Autodesk Fusion 360 part; units mm, degrees
(part 2 of 5)
extrude "B Facet 45 Opening 2" cut sketch "B Facet 45 Triangle 2" against normal blind 4.7 bodies 4 in component "B Moving Body"
fillet "B Facet 45 Aperture Root Radii" radius 1.5 6 edges at (-120, 35.1319, 67.7522) (-56.8709, 35.1319, 67.7522) (-120, 65.2593, 37.6247) (-110.9231, 67.7522, 35.1319) (-59.6927, 43.3032, 59.5808) (-84.1416, 67.7522, 35.1319) on bodies 4 in component "B Moving Body"
ref_plane "WorkPlane5" through (12.125, 0, 0) normal (0, 0, 1) x (1, 0, 0) in component "B Moving Body"
ref_plane "WorkPlane6" through (12.125, 0, 75) normal (0, 0, 1) x (1, 0, 0) in component "B Moving Body"
sketch "B Facet 90 Triangle 1" plane through (0, 0, 75) normal (0, 0, 1) x (1, 0, 0) in component "B Moving Body"
  line L0 (17.1665, -27.066) -> (-36.9655, 27.066) construction
  line L1 (-36.9655, 27.066) -> (-53.4167, -27.066) construction
  line L2 (-53.4167, -27.066) -> (17.1665, -27.066) construction
  line L3 (7.5097, -23.066) -> (-35.0777, 19.5214)
  line L4 (-35.0777, 19.5214) -> (-48.0205, -23.066)
  line L5 (-48.0205, -23.066) -> (7.5097, -23.066)
  dimension "d384" = 17.1665
  dimension "d385" = 27.066
  dimension "d386" = 36.9655
  dimension "d387" = 27.066
  dimension "d388" = 53.4167
  dimension "d389" = 27.066
  dimension "d390" = -4
  measures "d384" horizontal distance of origin L0.start
  measures "d385" vertical distance of origin L0.start
  measures "d386" horizontal distance of origin L0.end
  measures "d387" vertical distance of origin L0.end
  measures "d388" horizontal distance of origin L1.end
  measures "d389" vertical distance of origin L1.end
extrude "B Facet 90 Opening 1" cut sketch "B Facet 90 Triangle 1" against normal blind 4.7 bodies 4 in component "B Moving Body"
sketch "B Facet 90 Triangle 2" plane through (0, 0, 75) normal (0, 0, 1) x (1, 0, 0) in component "B Moving Body"
  line L0 (-36.9655, 27.066) -> (-53.4167, -27.066) construction
  line L1 (-53.4167, -27.066) -> (-124, 27.066) construction
  line L2 (-124, 27.066) -> (-36.9655, 27.066) construction
  line L3 (-42.3618, 23.066) -> (-55.5648, -20.3777)
  line L4 (-55.5648, -20.3777) -> (-112.2115, 23.066)
  line L5 (-112.2115, 23.066) -> (-42.3618, 23.066)
  dimension "d393" = 36.9655
  dimension "d394" = 27.066
  dimension "d395" = 53.4167
  dimension "d396" = 27.066
  dimension "d397" = 124
  dimension "d398" = 27.066
  dimension "d399" = 4
  measures "d393" horizontal distance of origin L0.start
  measures "d394" vertical distance of origin L0.start
  measures "d395" horizontal distance of origin L0.end
  measures "d396" vertical distance of origin L0.end
  measures "d397" horizontal distance of origin L1.end
  measures "d398" vertical distance of origin L1.end
extrude "B Facet 90 Opening 2" cut sketch "B Facet 90 Triangle 2" against normal blind 4.7 bodies 4 in component "B Moving Body"
sketch "B Facet 90 Triangle 3" plane through (0, 0, 75) normal (0, 0, 1) x (1, 0, 0) in component "B Moving Body"
  line L0 (-53.4167, -27.066) -> (-124, 27.066) construction
  line L1 (-124, 27.066) -> (-124, -27.066) construction
  line L2 (-124, -27.066) -> (-53.4167, -27.066) construction
  line L3 (-65.2053, -23.066) -> (-120, 18.9574)
  line L4 (-120, 18.9574) -> (-120, -23.066)
  line L5 (-120, -23.066) -> (-65.2053, -23.066)
  dimension "d402" = 53.4167
  dimension "d403" = 27.066
  dimension "d404" = 124
  dimension "d405" = 27.066
  dimension "d406" = 124
  dimension "d407" = 27.066
  dimension "d408" = -4
  measures "d402" horizontal distance of origin L0.start
  measures "d403" vertical distance of origin L0.start
  measures "d404" horizontal distance of origin L0.end
  measures "d405" vertical distance of origin L0.end
  measures "d406" horizontal distance of origin L1.end
  measures "d407" vertical distance of origin L1.end
extrude "B Facet 90 Opening 3" cut sketch "B Facet 90 Triangle 3" against normal blind 4.7 bodies 4 in component "B Moving Body"
fillet "B Facet 90 Aperture Root Radii" radius 1.5 9 edges at (-120, -23.066, 72.75) (-65.2053, -23.066, 72.75) (-120, 18.9574, 72.75) (-112.2115, 23.066, 72.75) (-55.5648, -20.3777, 72.75) (-42.3618, 23.066, 72.75) (-48.0205, -23.066, 72.75) (7.5097, -23.066, 72.75) (-35.0777, 19.5214, 72.75) on bodies 4 in component "B Moving Body"
ref_plane "WorkPlane7" through (12.125, 0, 0) normal (0, -0.707107, 0.707107) x (1, 0, 0) in component "B Moving Body"
ref_plane "WorkPlane8" through (12.125, -53.033, 53.033) normal (0, -0.707107, 0.707107) x (1, 0, 0) in component "B Moving Body"
sketch "B Facet 135 Triangle 1" plane through (0, -53.033, 53.033) normal (0, -0.707107, 0.707107) x (1, 0, 0) in component "B Moving Body"
  line L0 (23.9949, 27.066) -> (62.2721, -27.066) construction
  line L1 (62.2721, -27.066) -> (-25.3367, 27.066) construction
  line L2 (-25.3367, 27.066) -> (23.9949, 27.066) construction
  line L3 (21.9244, 23.066) -> (47.6674, -13.34)
  line L4 (47.6674, -13.34) -> (-11.2532, 23.066)
  line L5 (-11.2532, 23.066) -> (21.9244, 23.066)
  dimension "d417" = 23.9949
  dimension "d418" = 27.066
  dimension "d419" = 62.2721
  dimension "d420" = 27.066
  dimension "d421" = 25.3367
  dimension "d422" = 27.066
  dimension "d423" = 4
  measures "d417" horizontal distance of origin L0.start
  measures "d418" vertical distance of origin L0.start
  measures "d419" horizontal distance of origin L0.end
  measures "d420" vertical distance of origin L0.end
  measures "d421" horizontal distance of origin L1.end
  measures "d422" vertical distance of origin L1.end
extrude "B Facet 135 Opening 1" cut sketch "B Facet 135 Triangle 1" against normal blind 4.7 bodies 4 in component "B Moving Body"
sketch "B Facet 135 Triangle 2" plane through (0, -53.033, 53.033) normal (0, -0.707107, 0.707107) x (1, 0, 0) in component "B Moving Body"
  line L0 (62.2721, -27.066) -> (-25.3367, 27.066) construction
  line L1 (-25.3367, 27.066) -> (-61.9093, -27.066) construction
  line L2 (-61.9093, -27.066) -> (62.2721, -27.066) construction
  line L3 (48.1886, -23.066) -> (-24.1722, 21.6445)
  line L4 (-24.1722, 21.6445) -> (-54.3795, -23.066)
  line L5 (-54.3795, -23.066) -> (48.1886, -23.066)
  dimension "d426" = 62.2721
  dimension "d427" = 27.066
  dimension "d428" = 25.3367
  dimension "d429" = 27.066
  dimension "d430" = 61.9093
  dimension "d431" = 27.066
  dimension "d432" = -4
  measures "d426" horizontal distance of origin L0.start
  measures "d427" vertical distance of origin L0.start
  measures "d428" horizontal distance of origin L0.end
  measures "d429" vertical distance of origin L0.end
  measures "d430" horizontal distance of origin L1.end
  measures "d431" vertical distance of origin L1.end
extrude "B Facet 135 Opening 2" cut sketch "B Facet 135 Triangle 2" against normal blind 4.7 bodies 4 in component "B Moving Body"
sketch "B Facet 135 Triangle 3" plane through (0, -53.033, 53.033) normal (0, -0.707107, 0.707107) x (1, 0, 0) in component "B Moving Body"
  line L0 (-25.3367, 27.066) -> (-61.9093, -27.066) construction
  line L1 (-61.9093, -27.066) -> (-124, 27.066) construction
  line L2 (-124, 27.066) -> (-25.3367, 27.066) construction
  line L3 (-32.8665, 23.066) -> (-62.6909, -21.0779)
  line L4 (-62.6909, -21.0779) -> (-113.325, 23.066)
  line L5 (-113.325, 23.066) -> (-32.8665, 23.066)
  dimension "d435" = 25.3367
  dimension "d436" = 27.066
  dimension "d437" = 61.9093
  dimension "d438" = 27.066
  dimension "d439" = 124
  dimension "d440" = 27.066
  dimension "d441" = 4
  measures "d435" horizontal distance of origin L0.start
  measures "d436" vertical distance of origin L0.start
  measures "d437" horizontal distance of origin L0.end
  measures "d438" vertical distance of origin L0.end
  measures "d439" horizontal distance of origin L1.end
  measures "d440" vertical distance of origin L1.end
extrude "B Facet 135 Opening 3" cut sketch "B Facet 135 Triangle 3" against normal blind 4.7 bodies 4 in component "B Moving Body"
sketch "B Facet 135 Triangle 4" plane through (0, -53.033, 53.033) normal (0, -0.707107, 0.707107) x (1, 0, 0) in component "B Moving Body"
  line L0 (-61.9093, -27.066) -> (-124, 27.066) construction
  line L1 (-124, 27.066) -> (-124, -27.066) construction
  line L2 (-124, -27.066) -> (-61.9093, -27.066) construction
  line L3 (-72.5843, -23.066) -> (-120, 18.272)
  line L4 (-120, 18.272) -> (-120, -23.066)
  line L5 (-120, -23.066) -> (-72.5843, -23.066)
  dimension "d444" = 61.9093
  dimension "d445" = 27.066
  dimension "d446" = 124
  dimension "d447" = 27.066
  dimension "d448" = 124
  dimension "d449" = 27.066
  dimension "d450" = -4
  measures "d444" horizontal distance of origin L0.start
  measures "d445" vertical distance of origin L0.start
  measures "d446" horizontal distance of origin L0.end
  measures "d447" vertical distance of origin L0.end
  measures "d448" horizontal distance of origin L1.end
  measures "d449" vertical distance of origin L1.end
extrude "B Facet 135 Opening 4" cut sketch "B Facet 135 Triangle 4" against normal blind 4.7 bodies 4 in component "B Moving Body"
fillet "B Facet 135 Aperture Root Radii" radius 1.5 12 edges at (-120, -67.7522, 35.1319) (-72.5843, -67.7522, 35.1319) (-120, -38.5218, 64.3623) (-113.325, -35.1319, 67.7522) (-62.6909, -66.3463, 36.5377) (-32.8665, -35.1319, 67.7522) (-54.3795, -67.7522, 35.1319) (48.1886, -67.7522, 35.1319) (-24.1722, -36.137, 66.747) (-11.2532, -35.1319, 67.7522) (47.6674, -60.8748, 42.0092) (21.9244, -35.1319, 67.7522) on bodies 4 in component "B Moving Body"
ref_plane "WorkPlane9" through (12.125, 0, 0) normal (0, -1, 0) x (1, 0, 0) in component "B Moving Body"
ref_plane "WorkPlane10" through (12.125, -75, 0) normal (0, -1, 0) x (1, 0, 0) in component "B Moving Body"
sketch "B Facet 180 Triangle 1" plane through (0, -75, 0) normal (0, -1, 0) x (-1, 0, 0) in component "B Moving Body"
  line L0 (-65.1005, -27.066) -> (-65.1005, 27.066) construction
  line L1 (-65.1005, 27.066) -> (-2.067, -27.066) construction
  line L2 (-2.067, -27.066) -> (-65.1005, -27.066) construction
  line L3 (-61.1005, -23.066) -> (-61.1005, 18.3583)
  line L4 (-61.1005, 18.3583) -> (-12.8644, -23.066)
  line L5 (-12.8644, -23.066) -> (-61.1005, -23.066)
  dimension "d459" = 65.1005
  dimension "d460" = 27.066
  dimension "d461" = 65.1005
  dimension "d462" = 27.066
  dimension "d463" = 2.067
  dimension "d464" = 27.066
  dimension "d465" = 4
  measures "d459" horizontal distance of origin L0.start
  measures "d460" vertical distance of origin L0.start
  measures "d461" horizontal distance of origin L0.end
  measures "d462" vertical distance of origin L0.end
  measures "d463" horizontal distance of origin L1.end
  measures "d464" vertical distance of origin L1.end
extrude "B Facet 180 Opening 1" cut sketch "B Facet 180 Triangle 1" against normal blind 4.7 bodies 4 in component "B Moving Body"
sketch "B Facet 180 Triangle 2" plane through (0, -75, 0) normal (0, -1, 0) x (-1, 0, 0) in component "B Moving Body"
  line L0 (-65.1005, 27.066) -> (-2.067, -27.066) construction
  line L1 (-2.067, -27.066) -> (60.9665, 27.066) construction
  line L2 (60.9665, 27.066) -> (-65.1005, 27.066) construction
  line L3 (-54.3031, 23.066) -> (-2.067, -21.7934)
  line L4 (-2.067, -21.7934) -> (50.1691, 23.066)
  line L5 (50.1691, 23.066) -> (-54.3031, 23.066)
  dimension "d468" = 65.1005
  dimension "d469" = 27.066
  dimension "d470" = 2.067
  dimension "d471" = 27.066
  dimension "d472" = 60.9665
  dimension "d473" = 27.066
  dimension "d474" = -4
  measures "d468" horizontal distance of origin L0.start
  measures "d469" vertical distance of origin L0.start
  measures "d470" horizontal distance of origin L0.end
  measures "d471" vertical distance of origin L0.end
  measures "d472" horizontal distance of origin L1.end
  measures "d473" vertical distance of origin L1.end
extrude "B Facet 180 Opening 2" cut sketch "B Facet 180 Triangle 2" against normal blind 4.7 bodies 4 in component "B Moving Body"
sketch "B Facet 180 Triangle 3" plane through (0, -75, 0) normal (0, -1, 0) x (-1, 0, 0) in component "B Moving Body"
  line L0 (-2.067, -27.066) -> (60.9665, 27.066) construction
  line L1 (60.9665, 27.066) -> (124, -27.066) construction
  line L2 (124, -27.066) -> (-2.067, -27.066) construction
  line L3 (8.7304, -23.066) -> (60.9665, 21.7934)
  line L4 (60.9665, 21.7934) -> (113.2026, -23.066)
  line L5 (113.2026, -23.066) -> (8.7304, -23.066)
  dimension "d477" = 2.067
  dimension "d478" = 27.066
  dimension "d479" = 60.9665
  dimension "d480" = 27.066
  dimension "d481" = 124
  dimension "d482" = 27.066
  dimension "d483" = 4
  measures "d477" horizontal distance of origin L0.start
  measures "d478" vertical distance of origin L0.start
  measures "d479" horizontal distance of origin L0.end
  measures "d480" vertical distance of origin L0.end
  measures "d481" horizontal distance of origin L1.end
  measures "d482" vertical distance of origin L1.end
extrude "B Facet 180 Opening 3" cut sketch "B Facet 180 Triangle 3" against normal blind 4.7 bodies 4 in component "B Moving Body"
sketch "B Facet 180 Triangle 4" plane through (0, -75, 0) normal (0, -1, 0) x (-1, 0, 0) in component "B Moving Body"
  line L0 (60.9665, 27.066) -> (124, -27.066) construction
  line L1 (124, -27.066) -> (124, 27.066) construction
  line L2 (124, 27.066) -> (60.9665, 27.066) construction
  line L3 (71.7639, 23.066) -> (120, -18.3583)
  line L4 (120, -18.3583) -> (120, 23.066)
  line L5 (120, 23.066) -> (71.7639, 23.066)
  dimension "d486" = 60.9665
  dimension "d487" = 27.066
  dimension "d488" = 124
  dimension "d489" = 27.066
  dimension "d490" = 124
  dimension "d491" = 27.066
  dimension "d492" = -4
  measures "d486" horizontal distance of origin L0.start
  measures "d487" vertical distance of origin L0.start
  measures "d488" horizontal distance of origin L0.end
  measures "d489" vertical distance of origin L0.end
  measures "d490" horizontal distance of origin L1.end
  measures "d491" vertical distance of origin L1.end
extrude "B Facet 180 Opening 4" cut sketch "B Facet 180 Triangle 4" against normal blind 4.7 bodies 4 in component "B Moving Body"
fillet "B Facet 180 Aperture Root Radii" radius 1.5 12 edges at (-120, -72.75, -23.066) (-71.7639, -72.75, -23.066) (-120, -72.75, 18.3583) (-113.2026, -72.75, 23.066) (-60.9665, -72.75, -21.7934) (-8.7304, -72.75, 23.066) (-50.1691, -72.75, -23.066) (54.3031, -72.75, -23.066) (2.067, -72.75, 21.7934) (12.8644, -72.75, 23.066) (61.1005, -72.75, -18.3583) (61.1005, -72.75, 23.066) on bodies 4 in component "B Moving Body"
ref_plane "WorkPlane11" through (12.125, 0, 0) normal (0, -0.707107, -0.707107) x (1, 0, 0) in component "B Moving Body"
ref_plane "WorkPlane12" through (12.125, -53.033, -53.033) normal (0, -0.707107, -0.707107) x (1, 0, 0) in component "B Moving Body"
sketch "B Facet 225 Triangle 1" plane through (0, -53.033, -53.033) normal (0, -0.707107, -0.707107) x (1, 0, 0) in component "B Moving Body"
  line L0 (62.2721, 27.066) -> (23.9949, -27.066) construction
  line L1 (23.9949, -27.066) -> (0.1814, 27.066) construction
  line L2 (0.1814, 27.066) -> (62.2721, 27.066) construction
  line L3 (54.5447, 23.066) -> (24.81, -18.9852)
  line L4 (24.81, -18.9852) -> (6.311, 23.066)
  line L5 (6.311, 23.066) -> (54.5447, 23.066)
  dimension "d501" = 62.2721
  dimension "d502" = 27.066
  dimension "d503" = 23.9949
  dimension "d504" = 27.066
  dimension "d505" = 0.1814
  dimension "d506" = 27.066
  dimension "d507" = 4
  measures "d501" horizontal distance of origin L0.start
  measures "d502" vertical distance of origin L0.start
  measures "d503" horizontal distance of origin L0.end
  measures "d504" vertical distance of origin L0.end
  measures "d505" horizontal distance of origin L1.end
  measures "d506" vertical distance of origin L1.end
extrude "B Facet 225 Opening 1" cut sketch "B Facet 225 Triangle 1" against normal blind 4.7 bodies 4 in component "B Moving Body"
sketch "B Facet 225 Triangle 2" plane through (0, -53.033, -53.033) normal (0, -0.707107, -0.707107) x (1, 0, 0) in component "B Moving Body"
  line L0 (23.9949, -27.066) -> (0.1814, 27.066) construction
  line L1 (0.1814, 27.066) -> (-74.6684, -27.066) construction
  line L2 (-74.6684, -27.066) -> (23.9949, -27.066) construction
  line L3 (17.8653, -23.066) -> (-1.4863, 20.9235)
  line L4 (-1.4863, 20.9235) -> (-62.3117, -23.066)
  line L5 (-62.3117, -23.066) -> (17.8653, -23.066)
  dimension "d510" = 23.9949
  dimension "d511" = 27.066
  dimension "d512" = 0.1814
  dimension "d513" = 27.066
  dimension "d514" = 74.6684
  dimension "d515" = 27.066
  dimension "d516" = -4
  measures "d510" horizontal distance of origin L0.start
  measures "d511" vertical distance of origin L0.start
  measures "d512" horizontal distance of origin L0.end
  measures "d513" vertical distance of origin L0.end
  measures "d514" horizontal distance of origin L1.end
  measures "d515" vertical distance of origin L1.end
extrude "B Facet 225 Opening 2" cut sketch "B Facet 225 Triangle 2" against normal blind 4.7 bodies 4 in component "B Moving Body"
sketch "B Facet 225 Triangle 3" plane through (0, -53.033, -53.033) normal (0, -0.707107, -0.707107) x (1, 0, 0) in component "B Moving Body"
  line L0 (0.1814, 27.066) -> (-74.6684, -27.066) construction
  line L1 (-74.6684, -27.066) -> (-124, 27.066) construction
  line L2 (-124, 27.066) -> (0.1814, 27.066) construction
  line L3 (-12.1753, 23.066) -> (-74.1179, -21.7315)
  line L4 (-74.1179, -21.7315) -> (-114.9429, 23.066)
  line L5 (-114.9429, 23.066) -> (-12.1753, 23.066)
  dimension "d519" = 0.1814
  dimension "d520" = 27.066
  dimension "d521" = 74.6684
  dimension "d522" = 27.066
  dimension "d523" = 124
  dimension "d524" = 27.066
  dimension "d525" = 4
  measures "d519" horizontal distance of origin L0.start
  measures "d520" vertical distance of origin L0.start
  measures "d521" horizontal distance of origin L0.end
  measures "d522" vertical distance of origin L0.end
  measures "d523" horizontal distance of origin L1.end
  measures "d524" vertical distance of origin L1.end
extrude "B Facet 225 Opening 3" cut sketch "B Facet 225 Triangle 3" against normal blind 4.7 bodies 4 in component "B Moving Body"
sketch "B Facet 225 Triangle 4" plane through (0, -53.033, -53.033) normal (0, -0.707107, -0.707107) x (1, 0, 0) in component "B Moving Body"
  line L0 (-74.6684, -27.066) -> (-124, 27.066) construction
  line L1 (-124, 27.066) -> (-124, -27.066) construction
  line L2 (-124, -27.066) -> (-74.6684, -27.066) construction
  line L3 (-83.7255, -23.066) -> (-120, 16.7383)
  line L4 (-120, 16.7383) -> (-120, -23.066)
  line L5 (-120, -23.066) -> (-83.7255, -23.066)
  dimension "d528" = 74.6684
  dimension "d529" = 27.066
  dimension "d530" = 124
  dimension "d531" = 27.066
  dimension "d532" = 124
  dimension "d533" = 27.066
  dimension "d534" = -4
  measures "d528" horizontal distance of origin L0.start
  measures "d529" vertical distance of origin L0.start
  measures "d530" horizontal distance of origin L0.end
  measures "d531" vertical distance of origin L0.end
  measures "d532" horizontal distance of origin L1.end
  measures "d533" vertical distance of origin L1.end
extrude "B Facet 225 Opening 4" cut sketch "B Facet 225 Triangle 4" against normal blind 4.7 bodies 4 in component "B Moving Body"
fillet "B Facet 225 Aperture Root Radii" radius 1.5 12 edges at (-120, -35.1319, -67.7522) (-83.7255, -35.1319, -67.7522) (-120, -63.2778, -39.6062) (-114.9429, -67.7522, -35.1319) (-74.1179, -36.0755, -66.8085) (-12.1753, -67.7522, -35.1319) (-62.3117, -35.1319, -67.7522) (17.8653, -35.1319, -67.7522) (-1.4863, -66.2371, -36.6469) (6.311, -67.7522, -35.1319) (24.81, -38.0175, -64.8666) (54.5447, -67.7522, -35.1319) on bodies 4 in component "B Moving Body"
ref_plane "WorkPlane13" through (12.125, 0, 0) normal (0, 0, -1) x (1, 0, 0) in component "B Moving Body"
ref_plane "WorkPlane14" through (12.125, 0, -75) normal (0, 0, -1) x (1, 0, 0) in component "B Moving Body"
sketch "B Facet 270 Triangle 1" plane through (0, 0, -75) normal (0, 0, -1) x (-1, 0, 0) in component "B Moving Body"
  line L0 (-17.1665, -27.066) -> (36.9655, 27.066) construction
  line L1 (36.9655, 27.066) -> (53.4167, -27.066) construction
  line L2 (53.4167, -27.066) -> (-17.1665, -27.066) construction
  line L3 (-7.5097, -23.066) -> (35.0777, 19.5214)
  line L4 (35.0777, 19.5214) -> (48.0205, -23.066)
  line L5 (48.0205, -23.066) -> (-7.5097, -23.066)
  dimension "d543" = 17.1665
  dimension "d544" = 27.066
  dimension "d545" = 36.9655
  dimension "d546" = 27.066
  dimension "d547" = 53.4167
  dimension "d548" = 27.066
  dimension "d549" = 4
  measures "d543" horizontal distance of origin L0.start
  measures "d544" vertical distance of origin L0.start
  measures "d545" horizontal distance of origin L0.end
  measures "d546" vertical distance of origin L0.end
  measures "d547" horizontal distance of origin L1.end
  measures "d548" vertical distance of origin L1.end
extrude "B Facet 270 Opening 1" cut sketch "B Facet 270 Triangle 1" against normal blind 4.7 bodies 4 in component "B Moving Body"
sketch "B Facet 270 Triangle 2" plane through (0, 0, -75) normal (0, 0, -1) x (-1, 0, 0) in component "B Moving Body"
  line L0 (36.9655, 27.066) -> (53.4167, -27.066) construction
  line L1 (53.4167, -27.066) -> (124, 27.066) construction
  line L2 (124, 27.066) -> (36.9655, 27.066) construction
  line L3 (42.3618, 23.066) -> (55.5648, -20.3777)
  line L4 (55.5648, -20.3777) -> (112.2115, 23.066)
  line L5 (112.2115, 23.066) -> (42.3618, 23.066)
  dimension "d552" = 36.9655
  dimension "d553" = 27.066
  dimension "d554" = 53.4167
  dimension "d555" = 27.066
  dimension "d556" = 124
  dimension "d557" = 27.066
  dimension "d558" = -4
  measures "d552" horizontal distance of origin L0.start
  measures "d553" vertical distance of origin L0.start
  measures "d554" horizontal distance of origin L0.end
  measures "d555" vertical distance of origin L0.end
  measures "d556" horizontal distance of origin L1.end
  measures "d557" vertical distance of origin L1.end
extrude "B Facet 270 Opening 2" cut sketch "B Facet 270 Triangle 2" against normal blind 4.7 bodies 4 in component "B Moving Body"
sketch "B Facet 270 Triangle 3" plane through (0, 0, -75) normal (0, 0, -1) x (-1, 0, 0) in component "B Moving Body"
  line L0 (53.4167, -27.066) -> (124, 27.066) construction
  line L1 (124, 27.066) -> (124, -27.066) construction
  line L2 (124, -27.066) -> (53.4167, -27.066) construction
  line L3 (65.2053, -23.066) -> (120, 18.9574)
  line L4 (120, 18.9574) -> (120, -23.066)
  line L5 (120, -23.066) -> (65.2053, -23.066)
  dimension "d561" = 53.4167
  dimension "d562" = 27.066
  dimension "d563" = 124
  dimension "d564" = 27.066
  dimension "d565" = 124
  dimension "d566" = 27.066
  dimension "d567" = 4
  measures "d561" horizontal distance of origin L0.start
  measures "d562" vertical distance of origin L0.start
  measures "d563" horizontal distance of origin L0.end
  measures "d564" vertical distance of origin L0.end
  measures "d565" horizontal distance of origin L1.end
  measures "d566" vertical distance of origin L1.end
extrude "B Facet 270 Opening 3" cut sketch "B Facet 270 Triangle 3" against normal blind 4.7 bodies 4 in component "B Moving Body"
fillet "B Facet 270 Aperture Root Radii" radius 1.5 9 edges at (-120, -23.066, -72.75) (-120, 18.9574, -72.75) (-65.2053, -23.066, -72.75) (-112.2115, 23.066, -72.75) (-42.3618, 23.066, -72.75) (-55.5648, -20.3777, -72.75) (-48.0205, -23.066, -72.75) (-35.0777, 19.5214, -72.75) (7.5097, -23.066, -72.75) on bodies 4 in component "B Moving Body"
ref_plane "WorkPlane15" through (12.125, 0, 0) normal (0, 0.707107, -0.707107) x (1, 0, 0) in component "B Moving Body"
ref_plane "WorkPlane16" through (12.125, 53.033, -53.033) normal (0, 0.707107, -0.707107) x (1, 0, 0) in component "B Moving Body"
sketch "B Facet 315 Triangle 1" plane through (0, 53.033, -53.033) normal (0, 0.707107, -0.707107) x (1, 0, 0) in component "B Moving Body"
  line L0 (-43.7939, 27.066) -> (-82.0711, -27.066) construction
  line L1 (-82.0711, -27.066) -> (-124, 27.066) construction
  line L2 (-124, 27.066) -> (-43.7939, 27.066) construction
  line L3 (-51.5213, 23.066) -> (-82.2175, -20.3449)
  line L4 (-82.2175, -20.3449) -> (-115.8422, 23.066)
  line L5 (-115.8422, 23.066) -> (-51.5213, 23.066)
  dimension "d576" = 43.7939
  dimension "d577" = 27.066
  dimension "d578" = 82.0711
  dimension "d579" = 27.066
  dimension "d580" = 124
  dimension "d581" = 27.066
  dimension "d582" = 4
  measures "d576" horizontal distance of origin L0.start
  measures "d577" vertical distance of origin L0.start
  measures "d578" horizontal distance of origin L0.end
  measures "d579" vertical distance of origin L0.end
  measures "d580" horizontal distance of origin L1.end
  measures "d581" vertical distance of origin L1.end
extrude "B Facet 315 Opening 1" cut sketch "B Facet 315 Triangle 1" against normal blind 4.7 bodies 4 in component "B Moving Body"
sketch "B Facet 315 Triangle 2" plane through (0, 53.033, -53.033) normal (0, 0.707107, -0.707107) x (1, 0, 0) in component "B Moving Body"
  line L0 (-82.0711, -27.066) -> (-124, 27.066) construction
  line L1 (-124, 27.066) -> (-124, -27.066) construction
  line L2 (-124, -27.066) -> (-82.0711, -27.066) construction
  line L3 (-90.2289, -23.066) -> (-120, 15.3697)
  line L4 (-120, 15.3697) -> (-120, -23.066)
  line L5 (-120, -23.066) -> (-90.2289, -23.066)
  dimension "d585" = 82.0711
  dimension "d586" = 27.066
  dimension "d587" = 124
  dimension "d588" = 27.066
  dimension "d589" = 124
  dimension "d590" = 27.066
  dimension "d591" = -4
  measures "d585" horizontal distance of origin L0.start
  measures "d586" vertical distance of origin L0.start
  measures "d587" horizontal distance of origin L0.end
  measures "d588" vertical distance of origin L0.end
  measures "d589" horizontal distance of origin L1.end
  measures "d590" vertical distance of origin L1.end
extrude "B Facet 315 Opening 2" cut sketch "B Facet 315 Triangle 2" against normal blind 4.7 bodies 4 in component "B Moving Body"
fillet "B Facet 315 Aperture Root Radii" radius 1.5 6 edges at (-120, 67.7522, -35.1319) (-90.2289, 67.7522, -35.1319) (-120, 40.574, -62.3101) (-115.8422, 35.1319, -67.7522) (-82.2175, 65.828, -37.056) (-51.5213, 35.1319, -67.7522) on bodies 4 in component "B Moving Body"
component "A Housing" placed x (1, 0, 0) y (0, 1, 0) z (0, 0, 1) at (0, 0, 0)
component "B Moving Body" placed x (1, 0, 0) y (0, 1, 0) z (0, 0, 1) at (0, 0, 0)
equation "bodyWidth = 150 mm" comment "Regular octagon across flats; corner diameter is larger."
equation "bodyLength = 260 mm" comment "Overall straight length of the shared master blank."
equation "splitAngle = 45 deg" comment "Keep this lesson angle at45 degrees."
equation "faceGap = 1 mm" comment "Gap between the two printed joint faces."
equation "wall = 4.5 mm" comment "Integrated shell and side brace radial thickness."
equation "faceHalfWidth = bodyWidth * ( sqrt(2) - 1 ) / 2" comment "Half-width of each outer planar facet."
equation "memberWidth = 8 mm" comment "Nominal brace and corner chord width in a facet."
equation "nodeHalfWidth = faceHalfWidth - memberWidth / 2" comment "Chord centerlines measured from facet center."
equation "jointNodeQ = 7 mm" comment "First truss skeleton row from the center joint plane."
equation "endRim = 10 mm" comment "Uncut axial rim at each distant end."
equation "endNodeX = bodyLength / 2 - endRim + memberWidth / 2" comment "Last skeleton row before aperture inset."
equation "apertureRadius = 1.5 mm" comment "Rounded internal corners at triangular openings."
equation "spokeWidth = 10 mm" comment "Width of each deep bearing bulkhead spoke."
equation "spokeDepth = 18 mm" comment "Bulkhead depth normal to the diagonal joint face."
equation "carrierOD = 52 mm" comment "Outside of integrated A front bearing carrier."
equation "rearCarrierClearance = 46 mm" comment "Internal carrier relief above front bearing shoulder."
equation "tubeCornerChamfer = 0.5 mm" comment "Exposed outside octagon corner bevel."
equation "tubeRimChamfer = 0.3 mm" comment "End rim and print-contact edge relief."
equation "cordStation = bodyLength / 2 - endRim / 2" comment "Load-test cord port center measured along body X."
equation "bearingOD = 22 mm" comment "608 measured outside diameter."
equation "bearingID = 8 mm" comment "608 bore."
equation "bearingWidth = 7 mm" comment "608 width."
equation "seatAllowance = 0.2 mm" comment "Trial DIAMETRAL clearance; choose with printed coupon."
equation "seatDiameter = bearingOD + seatAllowance" comment "Measured fit controls this."
equation "coreOD = 44 mm" comment "Bearing holder outer diameter."
equation "raceRelief = 19.5 mm" comment "Outer-ring shoulder opening; verify seals."
equation "frontSeatDepth = 7.1 mm" comment "0.1 mm outer-ring axial allowance."
equation "rearSeatDepth = 7.2 mm" comment "0.2 mm outer-ring axial float."
equation "shoulder = 3 mm" comment "Backing behind each bearing seat."
equation "supportSpacer = 12 mm" comment "Purchased metal M3 spacer length."
equation "supportCircle = 34 mm" comment "Three M3 support bolts."
equation "supportSpacerOD = 6 mm" comment "Purchased spacer outside diameter."
equation "capThickness = 3 mm" comment "Both printed outer-ring retaining caps."
equation "m3Clearance = 3.3 mm" comment "M3 through holes."
equation "m4Clearance = 4.3 mm" comment "M4 through holes."
equation "qFront = faceGap / 2" comment "Front bearing starts at A mating face."
equation "qFrontBack = qFront + frontSeatDepth + shoulder" comment "End of integrated A holder."
equation "qRearBase = qFrontBack + supportSpacer" comment "Start of removable rear holder."
equation "qRearBearing = qRearBase + shoulder" comment "Rear bearing inner end."
equation "qRearEnd = qRearBearing + rearSeatDepth" comment "Rear holder outer end."
equation "bearingSpacing = qRearBearing - qFront" comment "Derived support-center spacing, not a bearing rating."
equation "mountOD = 76 mm" comment "B mount and F flange outside diameter."
equation "mountCircle = 64 mm" comment "Four M4 attachment holes."
equation "mountOpening = 50.3 mm" comment "B through opening."
equation "hubFace = -23 mm" comment "Metal hub flat mounting face."
equation "adapterThickness = 6 mm" comment "F flange and metal compression sleeve length."
equation "pilotDiameter = 50 mm" comment "F shallow centering pilot."
equation "pilotInside = 34 mm" comment "Clearance around metal hub."
equation "pilotHeight = 2 mm" comment "Short pilot only."
equation "hubHoleSpacing = 16 mm" comment "Metal Sonic hub square hole spacing."
equation "sleeveOD = 8 mm" comment "M4 metal compression sleeves."
equation "sleeveAllowance = 0.2 mm" comment "Trial DIAMETRAL sleeve clearance."
equation "shaftClearance = 8.5 mm" comment "F clearance hole; not a bearing."
equation "nutAF = 7.2 mm" comment "M4 nominal 7 AF nut trial pocket."
equation "nutDepth = 4 mm" comment "Open front M4 nut pocket."
equation "rootRadius = 1 mm" comment "Hub-to-wall blend."
equation "entryChamfer = 0.4 mm" comment "Assembly lead-in."
equation "bedRelief = 0.3 mm" comment "Bed-contact edge allowance."
equation "d59 = bodyWidth"
equation "d60 = bodyLength"
equation "d62 = splitAngle"
equation "d64 = -faceGap / 2"
equation "d65 = -faceGap / 2"
equation "d66 = wall"
equation "d67 = wall"
equation "d70 = bodyWidth / 2"
equation "d72 = abs(( 1 ) * ( ( ( 1 ) * jointNodeQ * sqrt(2) - bodyWidth / 2 * cos(0 deg) + ( ( -1 ) * nodeHalfWidth ) * sin(0 deg) ) + ( 0 ) * ( ( 1 ) * endNodeX - ( ( 1 ) * jointNodeQ * sqrt(2) - bodyWidth / 2 * cos(0 deg) + ( ( -1 ) * nodeHalfWidth ) * sin(0 deg) ) ) ) + ( 0 ) * ( ( -1 ) * nodeHalfWidth ))"
equation "d73 = abs(( 0 ) * ( ( ( 1 ) * jointNodeQ * sqrt(2) - bodyWidth / 2 * cos(0 deg) + ( ( -1 ) * nodeHalfWidth ) * sin(0 deg) ) + ( 0 ) * ( ( 1 ) * endNodeX - ( ( 1 ) * jointNodeQ * sqrt(2) - bodyWidth / 2 * cos(0 deg) + ( ( -1 ) * nodeHalfWidth ) * sin(0 deg) ) ) ) + ( -1 ) * ( ( -1 ) * nodeHalfWidth ))"
equation "d74 = abs(( 1 ) * ( ( ( 1 ) * jointNodeQ * sqrt(2) - bodyWidth / 2 * cos(0 deg) + ( ( 1 ) * nodeHalfWidth ) * sin(0 deg) ) + ( 0 ) * ( ( 1 ) * endNodeX - ( ( 1 ) * jointNodeQ * sqrt(2) - bodyWidth / 2 * cos(0 deg) + ( ( 1 ) * nodeHalfWidth ) * sin(0 deg) ) ) ) + ( 0 ) * ( ( 1 ) * nodeHalfWidth ))"
equation "d75 = abs(( 0 ) * ( ( ( 1 ) * jointNodeQ * sqrt(2) - bodyWidth / 2 * cos(0 deg) + ( ( 1 ) * nodeHalfWidth ) * sin(0 deg) ) + ( 0 ) * ( ( 1 ) * endNodeX - ( ( 1 ) * jointNodeQ * sqrt(2) - bodyWidth / 2 * cos(0 deg) + ( ( 1 ) * nodeHalfWidth ) * sin(0 deg) ) ) ) + ( -1 ) * ( ( 1 ) * nodeHalfWidth ))"
equation "d76 = abs(( 1 ) * ( ( ( 1 ) * jointNodeQ * sqrt(2) - bodyWidth / 2 * cos(0 deg) + ( ( -1 ) * nodeHalfWidth ) * sin(0 deg) ) + ( 0.666666666666667 ) * ( ( 1 ) * endNodeX - ( ( 1 ) * jointNodeQ * sqrt(2) - bodyWidth / 2 * cos(0 deg) + ( ( -1 ) * nodeHalfWidth ) * sin(0 deg) ) ) ) + ( 0 ) * ( ( -1 ) * nodeHalfWidth ))"
equation "d77 = abs(( 0 ) * ( ( ( 1 ) * jointNodeQ * sqrt(2) - bodyWidth / 2 * cos(0 deg) + ( ( -1 ) * nodeHalfWidth ) * sin(0 deg) ) + ( 0.666666666666667 ) * ( ( 1 ) * endNodeX - ( ( 1 ) * jointNodeQ * sqrt(2) - bodyWidth / 2 * cos(0 deg) + ( ( -1 ) * nodeHalfWidth ) * sin(0 deg) ) ) ) + ( -1 ) * ( ( -1 ) * nodeHalfWidth ))"
equation "d78 = -memberWidth / 2"
equation "d79 = -( wall + 0.2 mm )"
equation "d81 = abs(( 1 ) * ( ( ( 1 ) * jointNodeQ * sqrt(2) - bodyWidth / 2 * cos(0 deg) + ( ( 1 ) * nodeHalfWidth ) * sin(0 deg) ) + ( 0 ) * ( ( 1 ) * endNodeX - ( ( 1 ) * jointNodeQ * sqrt(2) - bodyWidth / 2 * cos(0 deg) + ( ( 1 ) * nodeHalfWidth ) * sin(0 deg) ) ) ) + ( 0 ) * ( ( 1 ) * nodeHalfWidth ))"
equation "d82 = abs(( 0 ) * ( ( ( 1 ) * jointNodeQ * sqrt(2) - bodyWidth / 2 * cos(0 deg) + ( ( 1 ) * nodeHalfWidth ) * sin(0 deg) ) + ( 0 ) * ( ( 1 ) * endNodeX - ( ( 1 ) * jointNodeQ * sqrt(2) - bodyWidth / 2 * cos(0 deg) + ( ( 1 ) * nodeHalfWidth ) * sin(0 deg) ) ) ) + ( -1 ) * ( ( 1 ) * nodeHalfWidth ))"
equation "d83 = abs(( 1 ) * ( ( ( 1 ) * jointNodeQ * sqrt(2) - bodyWidth / 2 * cos(0 deg) + ( ( -1 ) * nodeHalfWidth ) * sin(0 deg) ) + ( 0.666666666666667 ) * ( ( 1 ) * endNodeX - ( ( 1 ) * jointNodeQ * sqrt(2) - bodyWidth / 2 * cos(0 deg) + ( ( -1 ) * nodeHalfWidth ) * sin(0 deg) ) ) ) + ( 0 ) * ( ( -1 ) * nodeHalfWidth ))"
equation "d84 = abs(( 0 ) * ( ( ( 1 ) * jointNodeQ * sqrt(2) - bodyWidth / 2 * cos(0 deg) + ( ( -1 ) * nodeHalfWidth ) * sin(0 deg) ) + ( 0.666666666666667 ) * ( ( 1 ) * endNodeX - ( ( 1 ) * jointNodeQ * sqrt(2) - bodyWidth / 2 * cos(0 deg) + ( ( -1 ) * nodeHalfWidth ) * sin(0 deg) ) ) ) + ( -1 ) * ( ( -1 ) * nodeHalfWidth ))"
equation "d85 = abs(( 1 ) * ( ( ( 1 ) * jointNodeQ * sqrt(2) - bodyWidth / 2 * cos(0 deg) + ( ( 1 ) * nodeHalfWidth ) * sin(0 deg) ) + ( 0.833333333333333 ) * ( ( 1 ) * endNodeX - ( ( 1 ) * jointNodeQ * sqrt(2) - bodyWidth / 2 * cos(0 deg) + ( ( 1 ) * nodeHalfWidth ) * sin(0 deg) ) ) ) + ( 0 ) * ( ( 1 ) * nodeHalfWidth ))"
equation "d86 = abs(( 0 ) * ( ( ( 1 ) * jointNodeQ * sqrt(2) - bodyWidth / 2 * cos(0 deg) + ( ( 1 ) * nodeHalfWidth ) * sin(0 deg) ) + ( 0.833333333333333 ) * ( ( 1 ) * endNodeX - ( ( 1 ) * jointNodeQ * sqrt(2) - bodyWidth / 2 * cos(0 deg) + ( ( 1 ) * nodeHalfWidth ) * sin(0 deg) ) ) ) + ( -1 ) * ( ( 1 ) * nodeHalfWidth ))"
equation "d87 = memberWidth / 2"
equation "d88 = -( wall + 0.2 mm )"
equation "d90 = abs(( 1 ) * ( ( ( 1 ) * jointNodeQ * sqrt(2) - bodyWidth / 2 * cos(0 deg) + ( ( -1 ) * nodeHalfWidth ) * sin(0 deg) ) + ( 0.666666666666667 ) * ( ( 1 ) * endNodeX - ( ( 1 ) * jointNodeQ * sqrt(2) - bodyWidth / 2 * cos(0 deg) + ( ( -1 ) * nodeHalfWidth ) * sin(0 deg) ) ) ) + ( 0 ) * ( ( -1 ) * nodeHalfWidth ))"
equation "d91 = abs(( 0 ) * ( ( ( 1 ) * jointNodeQ * sqrt(2) - bodyWidth / 2 * cos(0 deg) + ( ( -1 ) * nodeHalfWidth ) * sin(0 deg) ) + ( 0.666666666666667 ) * ( ( 1 ) * endNodeX - ( ( 1 ) * jointNodeQ * sqrt(2) - bodyWidth / 2 * cos(0 deg) + ( ( -1 ) * nodeHalfWidth ) * sin(0 deg) ) ) ) + ( -1 ) * ( ( -1 ) * nodeHalfWidth ))"
equation "d92 = abs(( 1 ) * ( ( ( 1 ) * jointNodeQ * sqrt(2) - bodyWidth / 2 * cos(0 deg) + ( ( 1 ) * nodeHalfWidth ) * sin(0 deg) ) + ( 0.833333333333333 ) * ( ( 1 ) * endNodeX - ( ( 1 ) * jointNodeQ * sqrt(2) - bodyWidth / 2 * cos(0 deg) + ( ( 1 ) * nodeHalfWidth ) * sin(0 deg) ) ) ) + ( 0 ) * ( ( 1 ) * nodeHalfWidth ))"
equation "d93 = abs(( 0 ) * ( ( ( 1 ) * jointNodeQ * sqrt(2) - bodyWidth / 2 * cos(0 deg) + ( ( 1 ) * nodeHalfWidth ) * sin(0 deg) ) + ( 0.833333333333333 ) * ( ( 1 ) * endNodeX - ( ( 1 ) * jointNodeQ * sqrt(2) - bodyWidth / 2 * cos(0 deg) + ( ( 1 ) * nodeHalfWidth ) * sin(0 deg) ) ) ) + ( -1 ) * ( ( 1 ) * nodeHalfWidth ))"
equation "d94 = abs(( 1 ) * ( ( ( 1 ) * jointNodeQ * sqrt(2) - bodyWidth / 2 * cos(0 deg) + ( ( -1 ) * nodeHalfWidth ) * sin(0 deg) ) + ( 1 ) * ( ( 1 ) * endNodeX - ( ( 1 ) * jointNodeQ * sqrt(2) - bodyWidth / 2 * cos(0 deg) + ( ( -1 ) * nodeHalfWidth ) * sin(0 deg) ) ) ) + ( 0 ) * ( ( -1 ) * nodeHalfWidth ))"
equation "d95 = abs(( 0 ) * ( ( ( 1 ) * jointNodeQ * sqrt(2) - bodyWidth / 2 * cos(0 deg) + ( ( -1 ) * nodeHalfWidth ) * sin(0 deg) ) + ( 1 ) * ( ( 1 ) * endNodeX - ( ( 1 ) * jointNodeQ * sqrt(2) - bodyWidth / 2 * cos(0 deg) + ( ( -1 ) * nodeHalfWidth ) * sin(0 deg) ) ) ) + ( -1 ) * ( ( -1 ) * nodeHalfWidth ))"
equation "d96 = -memberWidth / 2"
equation "d97 = -( wall + 0.2 mm )"